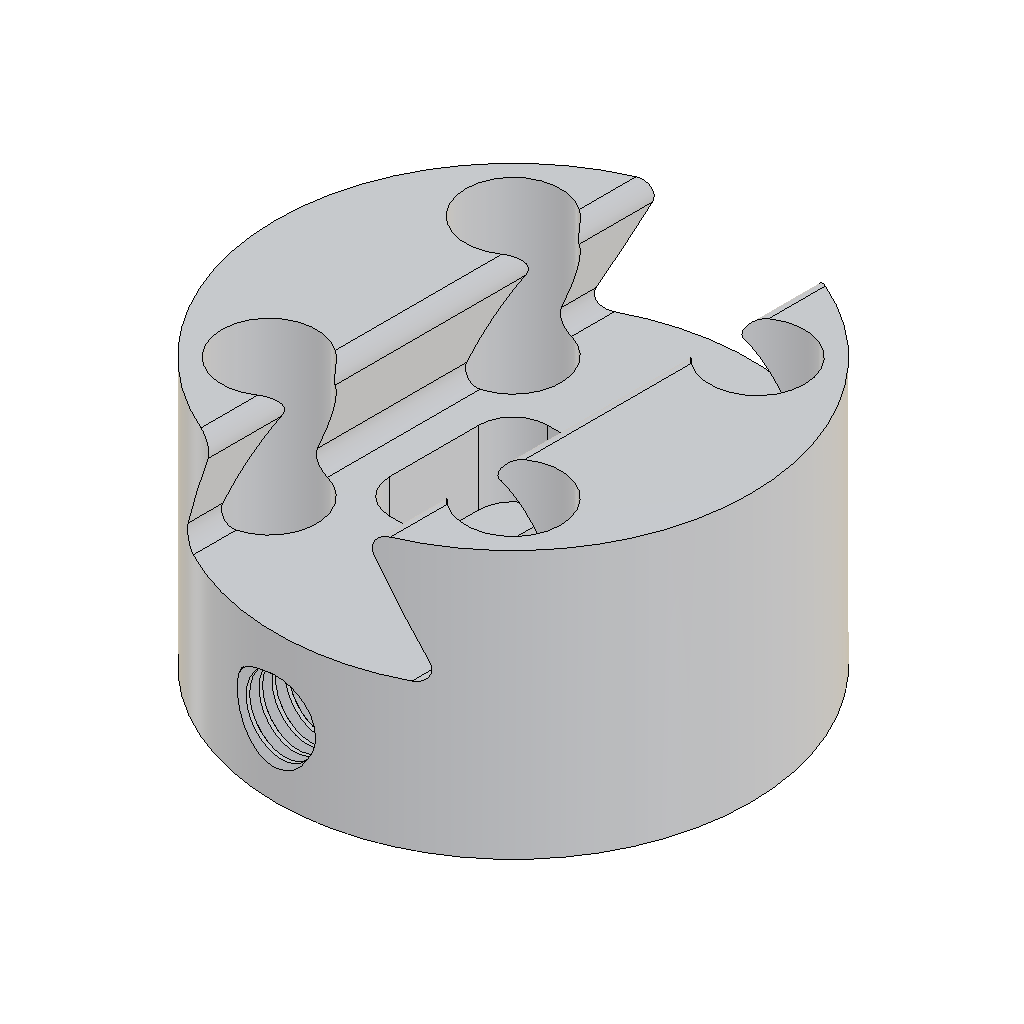
Wago Barewl (Autodesk Fusion 360 archive; units mm, degrees)
design "Luft Adapter"
part number: 2026-09-22-08-19-17-960
Autodesk Fusion 360 part; units mm, degrees
sketch "Sketch0" plane through (0, 0, 0) normal (0, 0, 1) x (1, 0, 0)
  circle A0 centre (0, 0) radius 27.5
  circle A1 centre (0, 0) radius 20 construction
  line L0 (0, 0) -> (19.4454, -19.4454) construction
  line L1 (0, 0) -> (27.5, 0) construction
  circle A2 centre (14.1421, -14.1421) radius 5.5
  circle A3 centre (14.1421, -14.1421) radius 3
  circle A4 centre (14.1421, 14.1421) radius 3
  circle A5 centre (14.1421, 14.1421) radius 5.5
  circle A6 centre (-14.1421, 14.1421) radius 3
  circle A7 centre (-14.1421, 14.1421) radius 5.5
  circle A8 centre (-14.1421, -14.1421) radius 3
  circle A9 centre (-14.1421, -14.1421) radius 5.5
  line L2 (0, 0) -> (0, 27.5) construction
  circle A10 centre (0, 20) radius 2.2
  circle A11 centre (0, 20) radius 2
  dimension "d84" = 55
  dimension "d85" = 40
  dimension "d86" = 45
  dimension "d87" = 27.5
  dimension "d88" = 11
  dimension "d89" = 6
  dimension "d91" = 360
  dimension "d92" = 4.4
  dimension "d97" = 4
  constraint coincident A0.centre A1.centre
  constraint horizontal L1
  constraint coincident A1 A2.centre
  constraint coincident L0 A2.centre
  constraint concentric A2 A3
  constraint coincident A0 L2.end
  constraint perpendicular L1 L2
  constraint coincident A1 A10.centre
  constraint coincident L2 A10.centre
  constraint concentric A10 A11
  measures "d84" diameter of A0
  measures "d85" diameter of A1
  measures "d86" angle of L0 L1
  measures "d87" distance of A0.centre L0.end
  measures "d88" diameter of A2
  measures "d89" diameter of A3
  measures "d92" diameter of A10
  measures "d97" diameter of A11
extrude "Extrude14" add sketch "Sketch0" along normal blind 2 contours A0 | A2 | A5 | A7 | A9
extrude "Extrude15" add sketch "Sketch0" along normal blind 11.5 contours A0
extrude "Extrude16" add sketch "Sketch0" along normal blind 16 contours A0 | A10
extrude "Extrude17" cut sketch "Sketch0" along normal blind 11.5 contours A10
thread "Thread4" "ISO Metric profile 4.0 M4x0.7 M4x0.7 6H" major diameter 4.1095 minor diameter 3.332 pitch 0.7 angle 60 modelled right hand crest width 0.193 on face at (1.9901, 19.8009, 14.5) crest through (1.666, 20, 11.675)
extrude "Extrude18" add 1 faces at (3.3701, 3.4671, 16) along direction (0, 0, 1) blind 15
sketch "Sketch11" plane through (0, 0, 0) normal (0, 1, 0) x (1, 0, 0)
  line L0 (-27.5, -31) -> (27.5, -31)
  line L1 (-27.5, -31) -> (27.5, -31)
  line L2 (-27.5, 0) -> (27.5, 0)
  line L3 (-1.8984, -16) -> (-0.6751, -16)
  line L4 (1.7261, -16) -> (-0.3837, -16)
  line L5 (19.6421, -31) -> (8.6421, -31)
  line L6 (19.6421, -31) -> (8.6421, -31)
  line L7 (-8.6421, -31) -> (-19.6421, -31)
  line L8 (-8.6421, -31) -> (-19.6421, -31)
  line L9 (19.6421, -31) -> (8.6421, -31)
  line L10 (8.6421, -2) -> (19.6421, -2)
  line L11 (-8.6421, -31) -> (-19.6421, -31)
  line L12 (-19.6421, -2) -> (-8.6421, -2)
  line L13 (8.6421, -31) -> (15, -17)
  line L14 (15, -17) -> (-15, -17)
  line L15 (-15, -17) -> (-8.6421, -31)
  circle A0 centre (10.9708, -29.5) radius 1.5
  circle A1 centre (-10.9708, -29.5) radius 1.5
  circle A2 centre (12.6714, -18.5) radius 1.5
  circle A3 centre (-12.6714, -18.5) radius 1.5
  line L16 (0, -31) -> (0, -3)
  dimension "d106" = 1
  dimension "d107" = 30
  dimension "d108" = 3
  dimension "d109" = 3
  dimension "d110" = 3
  dimension "d111" = 3
  constraint coincident L5.end L6.end
  constraint coincident L7.start L8.start
  constraint horizontal L14
  constraint tangent L6 A0
  constraint tangent L13 A0
  constraint tangent L8 A1
  constraint tangent L15 A1
  constraint tangent L13 A2
  constraint tangent L14 A2
  constraint tangent L14 A3
  constraint tangent L15 A3
  constraint midpoint L0 L16.start
  constraint perpendicular L4 L16
  constraint midpoint L14 L16
  measures "d106" distance of L4 L14
  measures "d107" distance of L13.end L14.end
  measures "d108" diameter of A0
  measures "d109" diameter of A1
  measures "d110" diameter of A2
  measures "d111" diameter of A3
extrude "Extrude19" cut sketch "Sketch11" along normal through all and the other way through all contours L0 L1 L14 L15 A3 L16 | L0 L1 L7 L8 L11 L15 A1 | L0 L1 L13 L14 A2 L16 | L0 L1 L5 L6 L9 L13 A0 | A3 | A2
sketch "Sketch12" plane through (0, 0, 0) normal (0, 1, 0) x (1, 0, 0)
  line L0 (12.6714, -17) -> (-12.6714, -17)
  line L1 (0, 0) -> (0, -17) construction
  circle A0 centre (0, -8.5) radius 5
  dimension "d114" = 10
  constraint coincident L1.start origin
  constraint midpoint L0 L1.end
  constraint midpoint L1 A0.centre
  measures "d114" diameter of A0
extrude "Extrude20" cut sketch "Sketch12" against normal through all
sketch "Sketch13" plane through (0, 0, 17) normal (0, 0, 1) x (-1, 0, 0)
  spline S0 degree 3 poles (0.6751, -21.5231) (0.7974, -21.485) (0.915, -21.4328) (1.1361, -21.303) (1.2389, -21.2258) (1.5043, -20.9764) (1.6418, -20.7816) (1.8383, -20.3414) (1.892, -20.099) (1.9039, -19.5975) (1.8582, -19.3434) (1.6688, -18.8578) (1.5234, -18.6326) (1.339, -18.4415) knots -0.378679 -0.378679 -0.378679 -0.378679 -0.340079 -0.340079 -0.301481 -0.301481 -0.230429 -0.230429 -0.156495 -0.156495 -0.079684 -0.079684 0 0 0 0
  arc A0 (-1.6117, -20.4218) -> (0.6751, -21.5231) centre (0, -20) ccw
  spline S1 degree 3 poles (0.3837, -17.9814) (0.2132, -17.9653) (0.0415, -17.9706) (-0.2965, -18.025) (-0.4613, -18.0738) (-0.8401, -18.2427) (-1.0421, -18.3829) (-1.3746, -18.7257) (-1.5046, -18.9228) (-1.6785, -19.347) (-1.7241, -19.5689) (-1.7279, -20.0082) (-1.6897, -20.2217) (-1.6117, -20.4218) knots -0.376945 -0.376945 -0.376945 -0.376945 -0.325784 -0.325784 -0.27462 -0.27462 -0.201752 -0.201752 -0.131694 -0.131694 -0.064444 -0.064444 0 0 0 0
  arc A1 (1.339, -18.4415) -> (0.3837, -17.9814) centre (0, -20) ccw
  arc A2 (12.6714, -8.8424) -> (12.6714, -19.4418) centre (14.1421, -14.1421) ccw
  line L0 (12.6714, -8.8424) -> (12.6714, 8.8424)
  arc A3 (12.6714, 19.4418) -> (12.6714, 8.8424) centre (14.1421, 14.1421) ccw
  line L1 (12.6714, 19.4418) -> (12.6714, 24.4067)
  arc A4 (12.6714, 24.4067) -> (-12.6714, 24.4067) centre (0, 0) ccw
  line L2 (-12.6714, 24.4067) -> (-12.6714, 19.4418)
  arc A5 (-12.6714, 8.8424) -> (-12.6714, 19.4418) centre (-14.1421, 14.1421) ccw
  line L3 (-12.6714, 8.8424) -> (-12.6714, -8.8424)
  arc A6 (-12.6714, -19.4418) -> (-12.6714, -8.8424) centre (-14.1421, -14.1421) ccw
  line L4 (-12.6714, -19.4418) -> (-12.6714, -24.4067)
  arc A7 (-12.6714, -24.4067) -> (12.6714, -24.4067) centre (0, 0) ccw
  line L5 (12.6714, -24.4067) -> (12.6714, -19.4418)
  line L6 (14.1421, -14.1421) -> (-14.1421, -14.1421)
  line L7 (-14.1421, -14.1421) -> (-14.1421, 14.1421)
  line L8 (-14.1421, 14.1421) -> (14.1421, 14.1421)
  line L9 (14.1421, 14.1421) -> (14.1421, -14.1421)
  line L10 (-9.1421, 9.1421) -> (9.1421, 9.1421)
  line L11 (9.1421, 9.1421) -> (9.1421, -9.1421)
  line L12 (9.1421, -9.1421) -> (-9.1421, -9.1421)
  line L13 (-9.1421, -9.1421) -> (-9.1421, 9.1421)
  dimension "d116" = 5
  constraint horizontal L6
  constraint vertical L7
  constraint horizontal L8
  constraint vertical L9
  constraint coincident A5.centre L7.end
  constraint coincident A2.centre L6.start
extrude "Extrude21" cut sketch "Sketch13" against normal up to surface (8.5 mm away) contours L10 L11 L12 L13
extrude "Extrude22" cut sketch "Sketch12" along normal up to surface (9.1421 mm away)
fillet "Fillet4" radius 4 4 edges at (9.1421, -9.1421, 12.75) (-9.1421, -9.1421, 12.75) (-9.1421, 9.1421, 12.75) (9.1421, 9.1421, 12.75)
thread "Thread5" "ISO Metric profile 10.0 M10x1.5 M10x1.5 6H" major diameter 10.198 minor diameter 8.526 pitch 1.5 angle 60 modelled right hand crest width 0.4094 on face at (-4.9716, -12.0657, 7.9679) from (0, -12.5003, 8.5) to (0, -27.5003, 8.5) crest through (4.263, 8.7671, 8.5)
equation "d87 = ( 55 / 2 ) * 1 mm"
